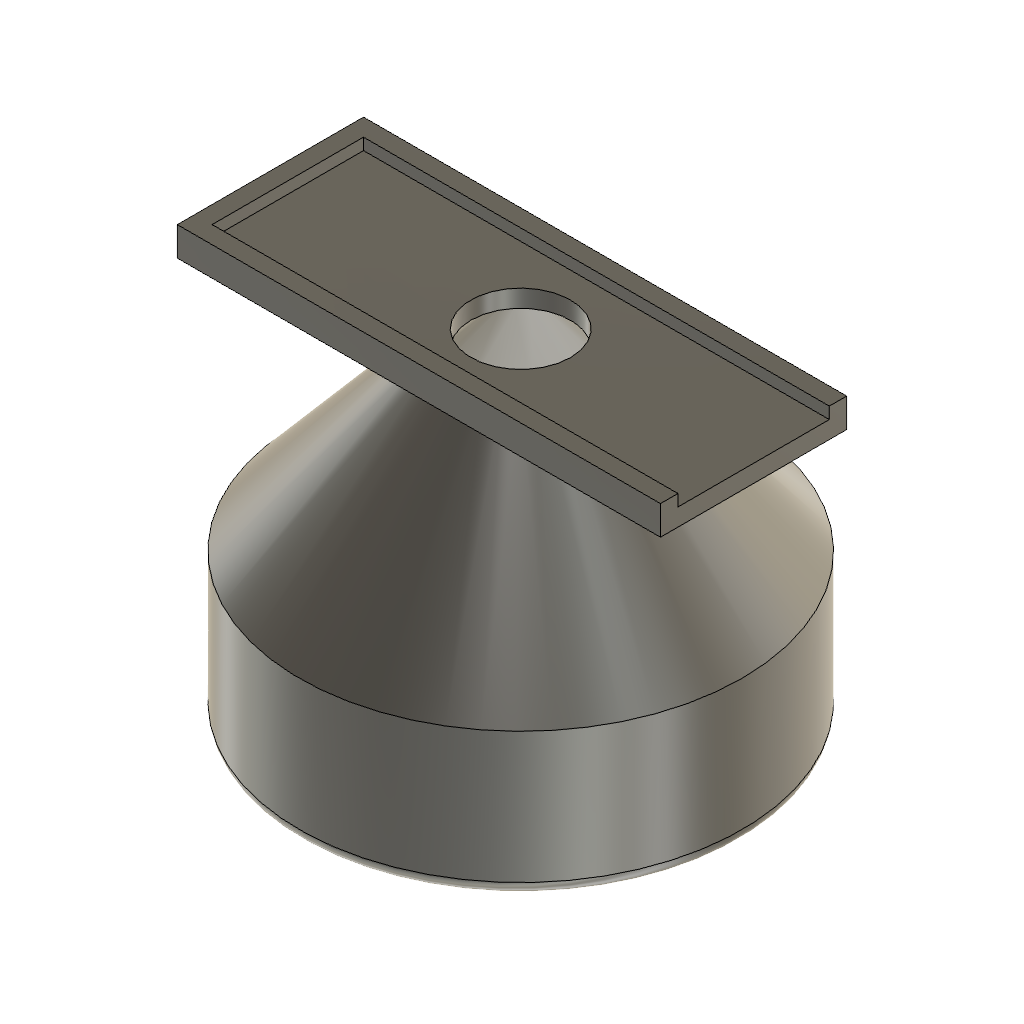
Frame (Autodesk Fusion 360 design; units mm, degrees)
Autodesk Fusion 360 part; units mm, degrees
sketch "Sketch2" plane through (0, 0, 0) normal (0, 0, 1) x (1, 0, 0)
  circle A0 centre (0, 0) radius 38
  dimension "d2" = 76
  constraint coincident A0.centre origin
  measures "d2" diameter of A0
extrude "Extrude3" add sketch "Sketch2" along normal blind 25
ref_plane "WorkPlane1" through (0, 0, 55) normal (0, 0, 1) x (1, 0, 0)
sketch "Sketch3" plane through (0, 0, 55) normal (0, 0, 1) x (1, 0, 0)
  circle A0 centre (0, 0) radius 12.5
  dimension "d11" = 25
  constraint coincident A0.centre origin
  measures "d11" diameter of A0
loft "Loft1" add profiles "Sketch3" section 1 face at (17.1829, 5.0634, 25) section 2
shell "Shell1" thickness 3 removed faces 2 at (17.1829, 5.0634, 0) at (-3.3879, -0.621, 55)
fillet "Fillet1" radius 2.5 1 edges at (-35.4284, -13.7414, 0)
sketch "Sketch5" plane through (0, 0, 55) normal (0, 0, 1) x (-1, 0, 0)
  circle A0 centre (0, 0) radius 8.5627
  circle A1 centre (0, 0) radius 12.5
  line L0 (-40, -13) -> (40, -13)
  line L1 (40, -13) -> (40, 13)
  line L2 (40, 13) -> (-40, 13)
  line L3 (-40, 13) -> (-40, -13)
  line L4 (-40, -13) -> (40, 13) construction
  line L5 (40, -13) -> (-40, 13) construction
  line L6 (43, 16) -> (-43, 16)
  line L7 (-43, 16) -> (-43, -16)
  line L8 (-43, -16) -> (43, -16)
  line L9 (43, -16) -> (43, 16)
  line L10 (-40, -13) -> (-40, -16)
  line L11 (-40, -16) -> (-40, 13)
  line L12 (-40, 13) -> (-40, 16)
  dimension "d15" = 80
  dimension "d16" = 26
  dimension "d17" = 3
  constraint horizontal L0
  constraint perpendicular L0 L1
  constraint parallel L0 L2
  constraint parallel L1 L3
  constraint coincident L4 A0.centre
  constraint coincident L5 A0.centre
  constraint coincident A0.centre A1.centre
  constraint coincident L8 L10.end
  constraint perpendicular L8 L10
  constraint coincident L6 L12.end
  constraint perpendicular L6 L12
  measures "d15" distance of L1.end L2.end
  measures "d16" distance of L0.end L1.end
extrude "Extrude4" add sketch "Sketch5" along normal blind 3 contours A1 | L0 L1 L2 L3 L11
extrude "Extrude5" add sketch "Sketch5" along normal blind 5 contours L0 L1 L2 L6 L8 L9 L10 L11 L12
